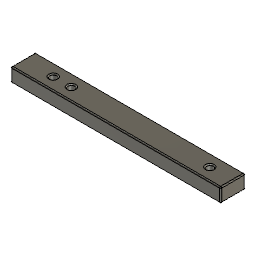
Bracket uniaxial 8p6mm (Autodesk Fusion 360 design; units mm, degrees)
Autodesk Fusion 360 part; units mm, degrees
sketch "Sketch1" plane through (0, 0, 0) normal (0, 0, 1) x (1, 0, 0)
  line L0 (-56, 5.9) -> (44, 5.9)
  line L1 (44, 5.9) -> (44, -5.9)
  line L2 (44, -5.9) -> (-56, -5.9)
  line L3 (-56, -5.9) -> (-56, 5.9)
  dimension "d1" = 100
  dimension "d2" = 11.8
  dimension "d3" = 5.9
  dimension "d14" = 44
  constraint horizontal L0
  constraint vertical L1
  constraint horizontal L2
  constraint vertical L3
  measures "d1" distance of L0.start L0.end
  measures "d2" distance of L0.start L2.end
  measures "d3" distance of origin L0
  measures "d14" distance of origin L1
sketch "Sketch2" plane through (0, 0, 7) normal (0, 0, 1) x (-1, 0, 0)
  line L0 (56, 6) -> (-44, 6)
  line L1 (-44, 6) -> (-44, -6)
  line L2 (-44, -6) -> (56, -6)
  line L3 (56, -6) -> (56, 6)
  line L4 (12, -6) -> (0, -6)
  line L5 (0, -6) -> (0, 6)
  line L6 (0, 6) -> (12, 6)
  line L7 (12, 6) -> (12, -6)
  dimension "d9" = 12
  dimension "d31" = 12
  constraint horizontal L4
  constraint vertical L5
  constraint horizontal L6
  constraint vertical L7
  constraint coincident L0 L5.end
  constraint coincident L2 L4.start
  measures "d9" distance of L5 L7
  measures "d31" distance of origin L7
sketch "Sketch4" plane through (0, 0, 0) normal (0, 0, -1) x (1, 0, 0)
  line L0 (44, 6) -> (-56, 6)
  line L1 (-56, 6) -> (-56, -6)
  line L2 (-56, -6) -> (44, -6)
  line L3 (44, -6) -> (44, 6)
  circle A0 centre (33, 0) radius 1.6
  line L4 (0, -19) -> (0, -18.2705)
  line L5 (0, -18.2705) -> (0, 20) construction
  circle A1 centre (-33, 0) radius 1.6
  circle A2 centre (-41.6, 0) radius 1.6
  circle A3 centre (-37, 0) radius 1.5
  line L6 (-60, 0) -> (-11.543, 0) construction
  dimension "d15" = 3.2
  dimension "d17" = 33
  dimension "d18" = 6
  dimension "d23" = 3.2
  dimension "d24" = 6
  dimension "d25" = 8.6
  dimension "d28" = 3
  dimension "d29" = 6
  dimension "d30" = 4
  dimension "d35" = 66
  constraint vertical L4
  constraint parallel L4 L5
  constraint symmetric A0 L5 A1
  constraint horizontal L6
  measures "d15" diameter of A0
  measures "d17" horizontal distance of origin A0.centre
  measures "d18" distance of L2 A0.centre
  measures "d23" diameter of A2
  measures "d24" distance of L2 A2.centre
  measures "d25" distance of A1.centre A2.centre
  measures "d28" diameter of A3
  measures "d29" distance of L2 A3.centre
  measures "d30" distance of A1.centre A3.centre
  measures "d35" distance of A0.centre A1.centre
extrude "Extrude7" add sketch "Sketch1" along normal blind 6.8
extrude "Extrude8" cut sketch "Sketch4" against normal blind 6.8 contours A0 | A1 | A2
fillet "Fillet2" radius 0.5 12 edges at (-6, -5.9, 6.8) (-6, 5.9, 6.8) (-6, -5.9, 0) (-6, 5.9, 0) (44, 5.9, 3.4) (44, -5.9, 3.4) (44, 0, 6.8) (44, 0, 0) (-56, 5.9, 3.4) (-56, 0, 6.8) (-56, -5.9, 3.4) (-56, 0, 0)
fillet "Fillet3" radius 0.5 6 edges at (-43.0917, 0.5786, 6.8) (-34.4917, 0.5786, 6.8) (31.5083, 0.5786, 6.8) (-43.0917, -0.5786, 0) (-34.4917, -0.5786, 0) (31.5083, -0.5786, 0)
equation "d3 = d2 / 2"
